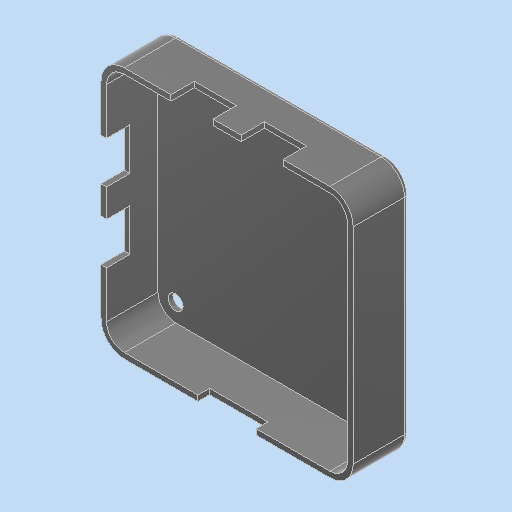
# Autodesk Inventor part: M5_stack-lower
Saved by Autodesk Inventor 2025.3 (Build 293356030, 356C)
## iProperties
Created: 2025-08-01
Part Number: M5_stack-lower
Material: 一般
Document SubType Name: Modeling
Designer: ibuki_ono
Density: 1 g/cm^3
Appearance: 滑らか - 黒
Author: ibuki_ono
Autodesk Inventor part; units mm, degrees
ref_plane "YZ Plane" through (0, 0, 0) normal (1, 0, 0) x (0, 1, 0)
ref_plane "XZ Plane" through (0, 0, 0) normal (0, 1, 0) x (-1, 0, 0)
ref_plane "XY Plane" through (0, 0, 0) normal (0, 0, 1) x (1, 0, 0)
sketch "スケッチ1" plane through (0, 0, 0) normal (0, 0, 1) x (1, 0, 0)
  line L0 (-27, -27) -> (27, -27)
  line L1 (27, -27) -> (27, 27)
  line L2 (27, 27) -> (-27, 27)
  line L3 (-27, 27) -> (-27, -27)
  line L4 (-27, -27) -> (27, 27) construction
  line L5 (27, -27) -> (-27, 27) construction
  point P0 (0, 0)
  dimension "d0" = 54
  dimension "d1" = 54
  constraints: 12 end point, 2 midpoint, 2 parallel, 1 horizontal, 1 perpendicular
  measures "d0" distance of L2.end L1.end
  measures "d1" distance of L1.end L0.end
extrude "押し出し1" add sketch "スケッチ1" along normal blind 12
fillet "フィレット1" radius 5 4 edges at (27, 27, 6) (-27, 27, 6) (27, -27, 6) (-27, -27, 6)
sketch "スケッチ2" plane through (0, 0, 12) normal (0, 0, 1) x (1, 0, 0)
  arc A0 (-27, -22) -> (-22, -27) centre (-22, -22) ccw projected
  line L0 (-22, -27) -> (22, -27) projected
  arc A1 (22, -27) -> (27, -22) centre (22, -22) ccw projected
  line L1 (27, -22) -> (27, 22) projected
  arc A2 (27, 22) -> (22, 27) centre (22, 22) ccw projected
  line L2 (22, 27) -> (-22, 27) projected
  arc A3 (-22, 27) -> (-27, 22) centre (-22, 22) ccw projected
  line L3 (-27, 22) -> (-27, -22) projected
  line L4 (-22, 25.8) -> (22, 25.8)
  arc A4 (25.8, 22) -> (22, 25.8) centre (22, 22) ccw
  line L5 (25.8, 22) -> (25.8, -22)
  arc A5 (22, -25.8) -> (25.8, -22) centre (22, -22) ccw
  line L6 (22, -25.8) -> (-22, -25.8)
  arc A6 (-25.8, -22) -> (-22, -25.8) centre (-22, -22) ccw
  line L7 (-25.8, -22) -> (-25.8, 22)
  arc A7 (-22, 25.8) -> (-25.8, 22) centre (-22, 22) ccw
  point P0 (0, 0)
  dimension "d5" = 1.2
  constraints: 8 end point, 8 point on circle, 4 centre point, 7 other
  measures "d5" distance between parallel lines of L2 L4
extrude "押し出し2" cut sketch "スケッチ2" against normal blind 11 contours L4 A4 L5 A5 L6 A6 L7 A7
fillet "フィレット2" radius 1 8 edges at (-25.5355, 25.5355, 0) (-27, 0, 0) (-25.5355, -25.5355, 0) (0, -27, 0) (25.5355, -25.5355, 0) (27, 0, 0) (25.5355, 25.5355, 0) (0, 27, 0)
sketch "スケッチ3" plane through (-22, 27, 12) normal (0, 1, 0) x (1, 0, 0)
  line L0 (0, 0) -> (44, 0) projected
  line L1 (34, 0) -> (25, 0)
  line L2 (25, 0) -> (25, 5)
  line L3 (25, 5) -> (34, 5)
  line L4 (34, 5) -> (34, 0)
  line L5 (19, 0) -> (10, 0)
  line L6 (10, 0) -> (10, 5)
  line L7 (10, 5) -> (19, 5)
  line L8 (19, 5) -> (19, 0)
  line L9 (49, 0) -> (49, 11) projected
  line L10 (-5, 11) -> (-5, 0) projected
  point P0 (22, 12)
  point P1 (10, 0)
  point P2 (25, 0)
  dimension "d9" = 9
  dimension "d10" = 5
  dimension "d11" = 9
  dimension "d12" = 5
  dimension "d13" = 15
  dimension "d14" = 15
  constraints: 16 end point, 4 parallel, 2 horizontal, 2 perpendicular, 2 point on line
  measures "d9" distance of L2.end L3.end
  measures "d10" distance of L1.end L2.end
  measures "d11" distance of L6.end L7.end
  measures "d12" distance of L5.end L6.end
  measures "d13" distance between parallel lines of L9 L4
  measures "d14" distance between parallel lines of L10 L6
extrude "押し出し3" cut sketch "スケッチ3" against normal up to surface (1.2 mm away)
pattern_circular "円形状パターン1" count 2 over 90 about axis through (0, 0, -10) along (0, 0, 1) of "押し出し3"
sketch "スケッチ4" plane through (-22, -27, 12) normal (0, -1, 0) x (1, 0, 0)
  line L0 (0, 0) -> (44, 0) projected
  line L1 (44, 0) -> (0, 0) projected
  line L2 (15.75, 0) -> (28.25, 0)
  line L3 (28.25, 0) -> (28.25, -2.5)
  line L4 (28.25, -2.5) -> (15.75, -2.5)
  line L5 (15.75, -2.5) -> (15.75, 0)
  point P0 (22, -12)
  point P1 (22, 0)
  point P2 (28.25, 0)
  point P3 (15.75, 0)
  dimension "d20" = 12.5
  dimension "d21" = 2.5
  constraints: 8 end point, 2 midpoint, 2 parallel, 1 horizontal, 1 perpendicular, 1 point on line
  measures "d20" distance of L3.end L4.end
  measures "d21" distance of L2.end L3.end
extrude "押し出し4" cut sketch "スケッチ4" against normal up to surface (1.2 mm away)
sketch "スケッチ5" plane through (0, 0, 0) normal (0, 0, -1) x (-1, 0, 0)
  line L0 (-27, 22) -> (-27, -22) projected
  line L1 (-22, -27) -> (22, -27) projected
  line L2 (27, -22) -> (27, 22) projected
  line L3 (-27, -22) -> (-26, -22) construction
  line L4 (-27, -22) -> (27, -22) construction
  point P0 (0, 0)
  point P1 (-22, -22)
  point P2 (22, -22)
  constraints: 2 end point, 2 point on line, 2 vertical alignment, 1 collinear
hole "穴1" at (22, -22, 0) at (-22, -22, 0) direction (0, 0, 1) diameter 3.2 end through all
sketch "スケッチ6" plane through (0, 0, 0) normal (0, 0, -1) x (-1, 0, 0)
  line L0 (-16, -16) -> (16, -16) construction
  line L1 (16, -16) -> (16, 16) construction
  line L2 (16, 16) -> (-16, 16) construction
  line L3 (-16, 16) -> (-16, -16) construction
  line L4 (-16, -16) -> (16, 16) construction
  line L5 (16, -16) -> (-16, 16) construction
  circle A0 centre (-16, 16) radius 4
  circle A1 centre (16, 16) radius 4
  circle A2 centre (-16, -16) radius 4
  circle A3 centre (16, -16) radius 4
  point P0 (0, 0)
  dimension "d31" = 32
  dimension "d32" = 32
  dimension "d33" = 8
  dimension "d34" = 8
  dimension "d35" = 8
  dimension "d36" = 8
  constraints: 12 end point, 4 centre point, 4 coincident, 2 midpoint, 2 parallel, 1 horizontal, 1 perpendicular
  measures "d31" distance of L2.end L1.end
  measures "d32" distance of L1.end L0.end
  measures "d33" diameter of A0
  measures "d34" diameter of A1
  measures "d35" diameter of A2
  measures "d36" diameter of A3
extrude "押し出し5" add sketch "スケッチ6" along normal blind 0.4
equation "\"d14\" = d13"
